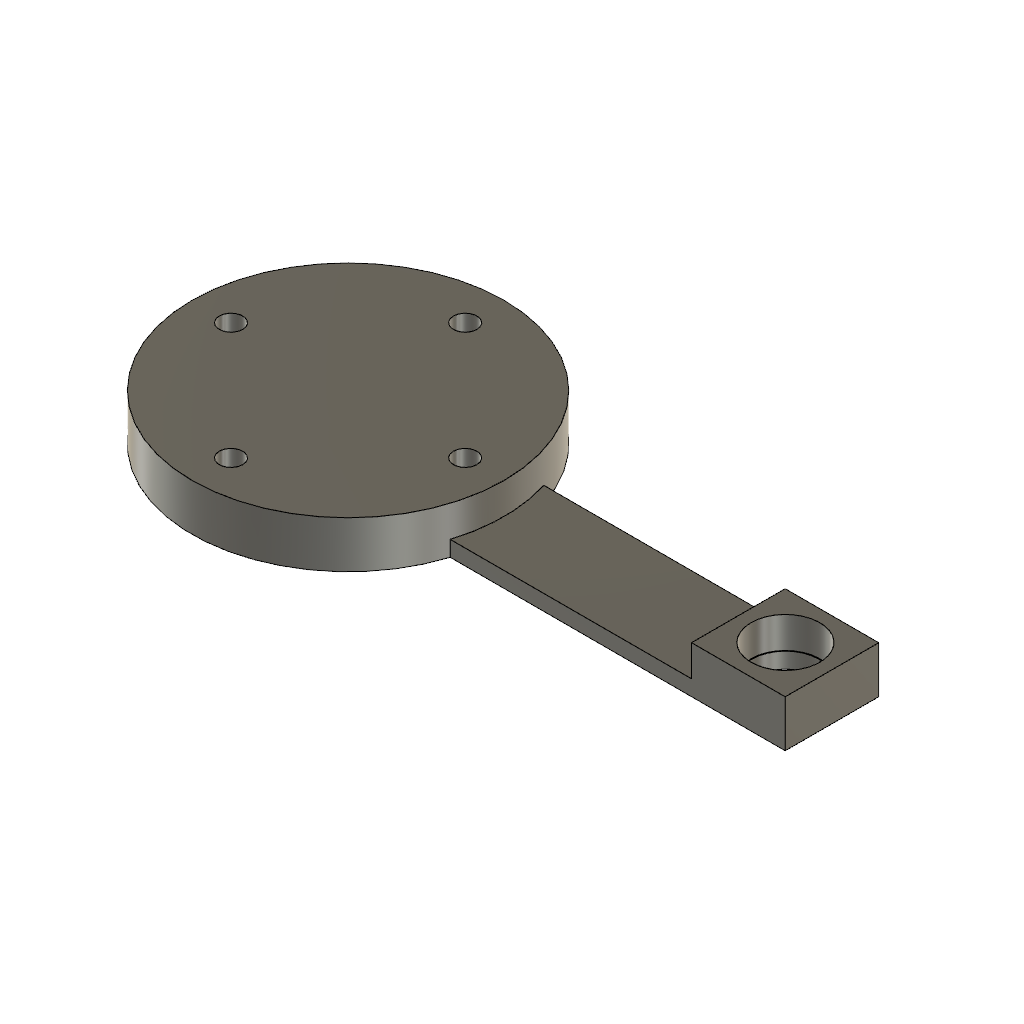
pastakahoidja2 (Autodesk Fusion 360 design; units mm, degrees)
part number: 2026-09-13-09-36-51-988
Autodesk Fusion 360 part; units mm, degrees
sketch "Sketch1" plane through (0, 0, 0) normal (0, 0, 1) x (1, 0, 0)
  circle A0 centre (15, 25) radius 20
  dimension "d1" = 40
  measures "d1" diameter of A0
cylinder "CylinderPrimitive1" add diameter 40 height 1 placed x (1, 0, 0) y (0, 1, 0) z (0, 0, 1) at (-9, 11, 0) makes body 1
move_face "MoveFace1" by (0.3492, 0.3492, 5) 1 faces at (-12.2978, 22.9263, 1) on bodies 1
sketch "Sketch3" plane through (0, 0, 6) normal (0, 0, 1) x (1, 0, 0)
  circle A0 centre (-9, 11) radius 20
  circle A1 centre (6, 11) radius 1.5
  circle A2 centre (-9, 26) radius 1.5
  circle A3 centre (-24, 11) radius 1.5
  circle A4 centre (-9, -4) radius 1.5
extrude "Extrude2" cut sketch "Sketch3" against normal through all contours A1 | A2 | A3 | A4 bodies 1
ref_plane "WorkPlane1" through (11, 0, 0) normal (1, 0, 0) x (0, 1, 0)
sketch "Sketch4" plane through (11, 0, 0) normal (1, 0, 0) x (0, 0, -1)
  line L0 (-24, -3) -> (46, -3)
  line L1 (46, -3) -> (46, 9)
  line L2 (46, 9) -> (-24, 9)
  line L3 (-24, 9) -> (-24, -3)
extrude "Extrude3" add sketch "Sketch4" along normal blind 2 separate body makes body 2
move_body "Move2" bodies 2 to x (0, 0, -1) y (0, 1, 0) z (1, 0, 0) at (55, 8, 13)
hole "Hole2" at (72.9908, 11.0393, 2) direction (0, 0, -1) diameter 8.6 depth 2 tip angle 118 bodies 2
copy_body "CopyPasteBodies1" bodies 2 makes body 3
move_body "Move4" bodies 3 to x (1, 0, 0) y (0, 1, 0) z (0, 0, 1) at (-2, 35, 0)
move_face "OffsetFaces1" offset -58 1 faces at (7, 44, 1.3333) on bodies 3
move_body "Move5" bodies 3 to x (1, 0, 0) y (0, 1, 0) z (0, 0, 1) at (2, -35, 2)
extrude "Extrude4" add 1 faces at (72.9969, 5.5798, 4) along direction (0, 0, 1) blind 2 on bodies 3 bodies 3
move_face "OffsetFaces2" offset 0.4 1 faces at (73.2052, 15.334, 4.6667) on bodies 3
move_face "OffsetFaces3" offset -0.5 1 faces at (73.1852, 7.1442, 4.6667) on bodies 3
combine "Combine1" operation add target body 2 tool bodies 1 3
ref_plane "WorkPlane2" through (39, 0, 0) normal (1, 0, 0) x (0, 1, 0)
sketch "Sketch6" plane through (39, 0, 0) normal (1, 0, 0) x (0, 0, -1)
  line L0 (5, 0) -> (17, 0)
  line L1 (17, 0) -> (17, 6)
  line L2 (17, 6) -> (5, 6)
  line L3 (5, 6) -> (5, 0)
extrude "Extrude5" cut sketch "Sketch6" along normal blind 28 bodies 2
split "Split1" by plane through (38.54, 0, 0) normal (1, 0, 0) bodies 2 makes body 4 at (48.5943, 10.906, 0)
extrude "Extrude6" cut 1 faces at (38.54, 9, 0.6667) along direction (-1, 0, 0) blind 26 on bodies 2 bodies 2
move_body "Move6" bodies 4 to x (1, 0, 0) y (0, 1, 0) z (0, 0, 1) at (-26, 0, 0)
combine "Combine2" operation add target body 4 tool bodies 2
